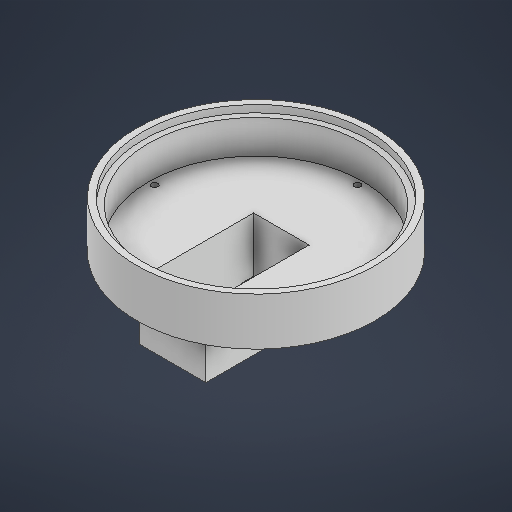
# Autodesk Inventor part: BaseS1P1.V4
Saved by Autodesk Inventor 2027.1 (Build 311270010, 270A)
## iProperties
Created: 2026-08-06
Part Number: BaseS1P1.V4
Material: Generic
Document SubType Name: Modeling
Designer: jose2
Density: 1 g/cm^3
Appearance: Default
Author: jose2
Autodesk Inventor part; units mm, degrees
ref_plane "YZ Plane" through (0, 0, 0) normal (1, 0, 0) x (0, 1, 0)
ref_plane "XZ Plane" through (0, 0, 0) normal (0, 1, 0) x (-1, 0, 0)
ref_plane "XY Plane" through (0, 0, 0) normal (0, 0, 1) x (1, 0, 0)
sketch "Sketch1" plane through (0, 0, 0) normal (0, 1, 0) x (-1, 0, 0)
  circle A0 centre (0, 0) radius 50
  circle A1 centre (0, 0) radius 47.4
  circle A2 centre (0, 0) radius 45
  dimension "d0" = 100
  dimension "d1" = 94.8
  dimension "d2" = 90
  constraints: 3 centre point, 3 coincident
  measures "d0" diameter of A0
  measures "d1" diameter of A1
  measures "d2" diameter of A2
extrude "Extrusion1" add sketch "Sketch1" along normal blind 17 contours A0
extrude "Extrusion2" add sketch "Sketch1" along normal blind 14 contours A1
extrude "Extrusion3" add sketch "Sketch1" against normal blind 3 contours A0 | A1 | A2
sketch "Sketch2" plane through (0, 0, 0) normal (0, 1, 0) x (1, 0, 0)
  circle A0 centre (0, 0) radius 4.5
  line L0 (-11.65, -33.36) -> (11.65, -33.36)
  line L1 (11.65, -33.36) -> (11.65, 10.64)
  line L2 (11.65, 10.64) -> (-11.65, 10.64)
  line L3 (-11.65, 10.64) -> (-11.65, -33.36)
  line L4 (-11.65, -33.36) -> (11.65, -33.36)
  line L5 (11.65, -33.36) -> (11.65, -18.36)
  line L6 (11.65, -18.36) -> (-11.65, -18.36)
  line L7 (-11.65, -18.36) -> (-11.65, -33.36)
  line L8 (-11.65, 10.64) -> (11.65, 10.64)
  line L9 (11.65, 10.64) -> (11.65, 5.64)
  line L10 (11.65, 5.64) -> (-11.65, 5.64)
  line L11 (-11.65, 5.64) -> (-11.65, 10.64)
  line L12 (-14, -35) -> (14, -35)
  line L13 (14, -35) -> (14, 13)
  line L14 (14, 13) -> (-14, 13)
  line L15 (-14, 13) -> (-14, -35)
  line L16 (-14, -35) -> (14, 13) construction
  line L17 (14, -35) -> (-14, 13) construction
  point P0 (0, -33.36)
  point P1 (0, -11)
  point P2 (-11.65, -18.36)
  dimension "d9" = 9
  dimension "d23" = 23.3
  dimension "d24" = 11.65
  dimension "d25" = 11.65
  dimension "d26" = 28
  dimension "d27" = 14
  dimension "d28" = 48
  dimension "d29" = 35
  constraints: 36 end point, 8 parallel, 4 horizontal, 4 perpendicular, 3 midpoint, 2 point on line, 1 centre point, 1 coincident
  measures "d9" diameter of A0
  measures "d23" distance of L1.end L2.end
  measures "d24" distance from line of L1 point (0, 0)
  measures "d25" distance from line of L3 point (0, 0)
  measures "d26" distance of L13.end L14.end
  measures "d27" distance from line of L13 point (0, 0)
  measures "d28" distance of L12.end L13.end
  measures "d29" distance from line of point (0, 0) L12
extrude "Extrusion4" cut sketch "Sketch2" against normal blind 25 contours A0 | L3 L10 L1 L6
extrude "Extrusion5" add sketch "Sketch2" against normal blind 23 contours L15 L14 L13 L12
sketch "Sketch3" plane through (0, -23, 0) normal (0, -1, 0) x (1, 0, 0)
  line L0 (14, 35) -> (14, -13) projected
  line L1 (-14, -13) -> (-14, 35) projected
  line L2 (14, 35) -> (-14, 35)
  line L3 (-14, 35) -> (-14, -13)
  line L4 (-14, -13) -> (14, -13)
  line L5 (14, -13) -> (14, 35)
  point P0 (0, 0)
  constraints: 8 end point, 2 parallel, 1 horizontal, 1 perpendicular
extrude "Extrusion6" add sketch "Sketch3" along normal blind 3
extrude "Extrusion7" cut sketch "Sketch2" against normal blind 5 contours L3 L6 L1 L0 | L3 L2 L1 L10
extrude "Extrusion8" cut sketch "Sketch2" against normal blind 30 contours A0 | L3 L10 L1 L6
sketch "Sketch4" plane through (0, 0, 0) normal (0, 1, 0) x (1, 0, 0)
  circle A0 centre (0, 0) radius 50
  circle A1 centre (0, 42.5494) radius 1.35
  circle A2 centre (-42.5494, 0) radius 1.35
  circle A3 centre (0, 0) radius 50
  circle A4 centre (0, -42.5494) radius 1.35
  circle A5 centre (0, 0) radius 50
  circle A6 centre (42.5494, 0) radius 1.35
  circle A7 centre (0, 0) radius 50
  dimension "d36" = 2.7
  dimension "d37" = 42.5494
  dimension "d40" = 360
  constraints: 8 centre point, 3 coincident, 15 other
  measures "d36" diameter of A1
  measures "d37" distance of A0.centre A1.centre
extrude "Extrusion9" cut sketch "Sketch4" against normal blind 30 contours A1 | A2 | A6
body "Solid1"
